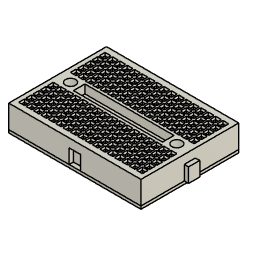
mini_breadboard (Autodesk Fusion 360 design; units mm, degrees)
Autodesk Fusion 360 part; units mm, degrees
(part 1 of 2)
sketch "Sketch1" plane through (0, 0, 0) normal (0, 1, 0) x (1, 0, 0)
  line L0 (0, 0) -> (46, 0)
  line L1 (46, 0) -> (46, -8)
  line L2 (46, -8) -> (0, -8)
  line L3 (0, -8) -> (0, 0)
  dimension "d3" = 46
  dimension "d4" = 8
  constraint horizontal L0
  constraint vertical L1
  constraint horizontal L2
  constraint vertical L3
  constraint coincident L0.start L3.end
  measures "d3" distance of L0.start L0.end
  measures "d4" distance of L0.start L2.end
extrude "Extrude1" add sketch "Sketch1" along normal blind 34 makes body 1
sketch "Sketch2" plane through (0, 0, 8) normal (0, 0, 1) x (-1, 0, 0)
  line L0 (0, 0) -> (-46, 0)
  line L1 (-46, 0) -> (-46, -34)
  line L2 (-46, -34) -> (0, -34)
  line L3 (0, -34) -> (0, 0)
  line L4 (-2, -31.5) -> (-3, -31.5)
  line L5 (-3, -31.5) -> (-3, -30.5)
  line L6 (-3, -30.5) -> (-2, -30.5)
  line L7 (-2, -30.5) -> (-2, -31.5)
  dimension "d11" = 1
  dimension "d12" = 1
  dimension "d38" = 2
  dimension "d39" = 2.5
  constraint horizontal L4
  constraint vertical L5
  constraint horizontal L6
  constraint vertical L7
  measures "d11" distance of L4.end L5.end
  measures "d12" distance of L5.end L6.end
  measures "d38" distance of L3 L7
  measures "d39" distance of L2 L4
extrude "Extrude2" cut sketch "Sketch2" against normal blind 3 contours L4 L5 L6 L7 bodies 1
chamfer "Chamfer1" distance 0.5 angle 45 4 edges at (2.5, 30.5, 8) (3, 31, 8) (2.5, 31.5, 8) (2, 31, 8) on bodies 1
pattern_linear "R-Pattern1" count 17 spacing 2.5625 along (1, 0, 0) count 5 spacing 2.5 along (0, -1, 0) of 9 faces at (2.6667, 31.8333, 7.8333) (1.6667, 31.1667, 7.8333) (2.3333, 31.5, 6.6667) (3.3333, 30.8333, 7.8333) (2.3333, 30.1667, 7.8333) (2.3333, 31.1667, 5) (3, 30.8333, 5.8333) (2.6667, 30.5, 6.6667) (2, 31.1667, 5.8333) on bodies 1
sketch "Sketch3" plane through (0, 0, 8) normal (0, 0, 1) x (-1, 0, 0)
  line L0 (-42.5, -22) -> (-44.5, -22)
  line L1 (-44.5, -22) -> (-44.5, -20)
  line L2 (-44.5, -20) -> (-42.5, -20)
  line L3 (-42.5, -20) -> (-42.5, -22)
  line L4 (-39.9375, -22) -> (-41.9375, -22)
  line L5 (-41.9375, -22) -> (-41.9375, -20)
  line L6 (-41.9375, -20) -> (-39.9375, -20)
  line L7 (-39.9375, -20) -> (-39.9375, -22)
  line L8 (-37.375, -22) -> (-39.375, -22)
  line L9 (-39.375, -22) -> (-39.375, -20)
  line L10 (-39.375, -20) -> (-37.375, -20)
  line L11 (-37.375, -20) -> (-37.375, -22)
  line L12 (-34.8125, -22) -> (-36.8125, -22)
  line L13 (-36.8125, -22) -> (-36.8125, -20)
  line L14 (-36.8125, -20) -> (-34.8125, -20)
  line L15 (-34.8125, -20) -> (-34.8125, -22)
  line L16 (-32.25, -22) -> (-34.25, -22)
  line L17 (-34.25, -22) -> (-34.25, -20)
  line L18 (-34.25, -20) -> (-32.25, -20)
  line L19 (-32.25, -20) -> (-32.25, -22)
  line L20 (-29.6875, -22) -> (-31.6875, -22)
  line L21 (-31.6875, -22) -> (-31.6875, -20)
  line L22 (-31.6875, -20) -> (-29.6875, -20)
  line L23 (-29.6875, -20) -> (-29.6875, -22)
  line L24 (-27.125, -22) -> (-29.125, -22)
  line L25 (-29.125, -22) -> (-29.125, -20)
  line L26 (-29.125, -20) -> (-27.125, -20)
  line L27 (-27.125, -20) -> (-27.125, -22)
  line L28 (-24.5625, -22) -> (-26.5625, -22)
  line L29 (-26.5625, -22) -> (-26.5625, -20)
  line L30 (-26.5625, -20) -> (-24.5625, -20)
  line L31 (-24.5625, -20) -> (-24.5625, -22)
  line L32 (-22, -22) -> (-24, -22)
  line L33 (-24, -22) -> (-24, -20)
  line L34 (-24, -20) -> (-22, -20)
  line L35 (-22, -20) -> (-22, -22)
  line L36 (-19.4375, -22) -> (-21.4375, -22)
  line L37 (-21.4375, -22) -> (-21.4375, -20)
  line L38 (-21.4375, -20) -> (-19.4375, -20)
  line L39 (-19.4375, -20) -> (-19.4375, -22)
  line L40 (-16.875, -22) -> (-18.875, -22)
  line L41 (-18.875, -22) -> (-18.875, -20)
  line L42 (-18.875, -20) -> (-16.875, -20)
  line L43 (-16.875, -20) -> (-16.875, -22)
  line L44 (-14.3125, -22) -> (-16.3125, -22)
  line L45 (-16.3125, -22) -> (-16.3125, -20)
  line L46 (-16.3125, -20) -> (-14.3125, -20)
  line L47 (-14.3125, -20) -> (-14.3125, -22)
  line L48 (-11.75, -22) -> (-13.75, -22)
  line L49 (-13.75, -22) -> (-13.75, -20)
  line L50 (-13.75, -20) -> (-11.75, -20)
  line L51 (-11.75, -20) -> (-11.75, -22)
  line L52 (-9.1875, -22) -> (-11.1875, -22)
  line L53 (-11.1875, -22) -> (-11.1875, -20)
  line L54 (-11.1875, -20) -> (-9.1875, -20)
  line L55 (-9.1875, -20) -> (-9.1875, -22)
  line L56 (-6.625, -22) -> (-8.625, -22)
  line L57 (-8.625, -22) -> (-8.625, -20)
  line L58 (-8.625, -20) -> (-6.625, -20)
  line L59 (-6.625, -20) -> (-6.625, -22)
  line L60 (-4.0625, -22) -> (-6.0625, -22)
  line L61 (-6.0625, -22) -> (-6.0625, -20)
  line L62 (-6.0625, -20) -> (-4.0625, -20)
  line L63 (-4.0625, -20) -> (-4.0625, -22)
  line L64 (-1.5, -22) -> (-3.5, -22)
  line L65 (-3.5, -22) -> (-3.5, -20)
  line L66 (-3.5, -20) -> (-1.5, -20)
  line L67 (-1.5, -20) -> (-1.5, -22)
  line L68 (-42.5, -24.5) -> (-44.5, -24.5)
  line L69 (-44.5, -24.5) -> (-44.5, -22.5)
  line L70 (-44.5, -22.5) -> (-42.5, -22.5)
  line L71 (-42.5, -22.5) -> (-42.5, -24.5)
  line L72 (-39.9375, -24.5) -> (-41.9375, -24.5)
  line L73 (-41.9375, -24.5) -> (-41.9375, -22.5)
  line L74 (-41.9375, -22.5) -> (-39.9375, -22.5)
  line L75 (-39.9375, -22.5) -> (-39.9375, -24.5)
  line L76 (-37.375, -24.5) -> (-39.375, -24.5)
  line L77 (-39.375, -24.5) -> (-39.375, -22.5)
  line L78 (-39.375, -22.5) -> (-37.375, -22.5)
  line L79 (-37.375, -22.5) -> (-37.375, -24.5)
  line L80 (-34.8125, -24.5) -> (-36.8125, -24.5)
  line L81 (-36.8125, -24.5) -> (-36.8125, -22.5)
  line L82 (-36.8125, -22.5) -> (-34.8125, -22.5)
  line L83 (-34.8125, -22.5) -> (-34.8125, -24.5)
  line L84 (-32.25, -24.5) -> (-34.25, -24.5)
  line L85 (-34.25, -24.5) -> (-34.25, -22.5)
  line L86 (-34.25, -22.5) -> (-32.25, -22.5)
  line L87 (-32.25, -22.5) -> (-32.25, -24.5)
  line L88 (-29.6875, -24.5) -> (-31.6875, -24.5)
  line L89 (-31.6875, -24.5) -> (-31.6875, -22.5)
  line L90 (-31.6875, -22.5) -> (-29.6875, -22.5)
  line L91 (-29.6875, -22.5) -> (-29.6875, -24.5)
  line L92 (-27.125, -24.5) -> (-29.125, -24.5)
  line L93 (-29.125, -24.5) -> (-29.125, -22.5)
  line L94 (-29.125, -22.5) -> (-27.125, -22.5)
  line L95 (-27.125, -22.5) -> (-27.125, -24.5)
  line L96 (-24.5625, -24.5) -> (-26.5625, -24.5)
  line L97 (-26.5625, -24.5) -> (-26.5625, -22.5)
  line L98 (-26.5625, -22.5) -> (-24.5625, -22.5)
  line L99 (-24.5625, -22.5) -> (-24.5625, -24.5)
  line L100 (-22, -24.5) -> (-24, -24.5)
  line L101 (-24, -24.5) -> (-24, -22.5)
  line L102 (-24, -22.5) -> (-22, -22.5)
  line L103 (-22, -22.5) -> (-22, -24.5)
  line L104 (-19.4375, -24.5) -> (-21.4375, -24.5)
  line L105 (-21.4375, -24.5) -> (-21.4375, -22.5)
  line L106 (-21.4375, -22.5) -> (-19.4375, -22.5)
  line L107 (-19.4375, -22.5) -> (-19.4375, -24.5)
  line L108 (-16.875, -24.5) -> (-18.875, -24.5)
  line L109 (-18.875, -24.5) -> (-18.875, -22.5)
  line L110 (-18.875, -22.5) -> (-16.875, -22.5)
  line L111 (-16.875, -22.5) -> (-16.875, -24.5)
  line L112 (-14.3125, -24.5) -> (-16.3125, -24.5)
  line L113 (-16.3125, -24.5) -> (-16.3125, -22.5)
  line L114 (-16.3125, -22.5) -> (-14.3125, -22.5)
  line L115 (-14.3125, -22.5) -> (-14.3125, -24.5)
  line L116 (-11.75, -24.5) -> (-13.75, -24.5)
  line L117 (-13.75, -24.5) -> (-13.75, -22.5)
  line L118 (-13.75, -22.5) -> (-11.75, -22.5)
  line L119 (-11.75, -22.5) -> (-11.75, -24.5)
  line L120 (-9.1875, -24.5) -> (-11.1875, -24.5)
  line L121 (-11.1875, -24.5) -> (-11.1875, -22.5)
  line L122 (-11.1875, -22.5) -> (-9.1875, -22.5)
  line L123 (-9.1875, -22.5) -> (-9.1875, -24.5)
  line L124 (-6.625, -24.5) -> (-8.625, -24.5)
  line L125 (-8.625, -24.5) -> (-8.625, -22.5)
  line L126 (-8.625, -22.5) -> (-6.625, -22.5)
  line L127 (-6.625, -22.5) -> (-6.625, -24.5)
  line L128 (-4.0625, -24.5) -> (-6.0625, -24.5)
  line L129 (-6.0625, -24.5) -> (-6.0625, -22.5)
  line L130 (-6.0625, -22.5) -> (-4.0625, -22.5)
  line L131 (-4.0625, -22.5) -> (-4.0625, -24.5)
  line L132 (-1.5, -24.5) -> (-3.5, -24.5)
  line L133 (-3.5, -24.5) -> (-3.5, -22.5)
  line L134 (-3.5, -22.5) -> (-1.5, -22.5)
  line L135 (-1.5, -22.5) -> (-1.5, -24.5)
  line L136 (-42.5, -27) -> (-44.5, -27)
  line L137 (-44.5, -27) -> (-44.5, -25)
  line L138 (-44.5, -25) -> (-42.5, -25)
  line L139 (-42.5, -25) -> (-42.5, -27)
  line L140 (-39.9375, -27) -> (-41.9375, -27)
  line L141 (-41.9375, -27) -> (-41.9375, -25)
  line L142 (-41.9375, -25) -> (-39.9375, -25)
  line L143 (-39.9375, -25) -> (-39.9375, -27)
  line L144 (-37.375, -27) -> (-39.375, -27)
  line L145 (-39.375, -27) -> (-39.375, -25)
  line L146 (-39.375, -25) -> (-37.375, -25)
  line L147 (-37.375, -25) -> (-37.375, -27)
  line L148 (-34.8125, -27) -> (-36.8125, -27)
  line L149 (-36.8125, -27) -> (-36.8125, -25)
  line L150 (-36.8125, -25) -> (-34.8125, -25)
  line L151 (-34.8125, -25) -> (-34.8125, -27)
  line L152 (-32.25, -27) -> (-34.25, -27)
  line L153 (-34.25, -27) -> (-34.25, -25)
  line L154 (-34.25, -25) -> (-32.25, -25)
  line L155 (-32.25, -25) -> (-32.25, -27)
  line L156 (-29.6875, -27) -> (-31.6875, -27)
  line L157 (-31.6875, -27) -> (-31.6875, -25)
  line L158 (-31.6875, -25) -> (-29.6875, -25)
  line L159 (-29.6875, -25) -> (-29.6875, -27)
  line L160 (-27.125, -27) -> (-29.125, -27)
  line L161 (-29.125, -27) -> (-29.125, -25)
  line L162 (-29.125, -25) -> (-27.125, -25)
  line L163 (-27.125, -25) -> (-27.125, -27)
  line L164 (-24.5625, -27) -> (-26.5625, -27)
  line L165 (-26.5625, -27) -> (-26.5625, -25)
  line L166 (-26.5625, -25) -> (-24.5625, -25)
  line L167 (-24.5625, -25) -> (-24.5625, -27)
  line L168 (-22, -27) -> (-24, -27)
  line L169 (-24, -27) -> (-24, -25)
  line L170 (-24, -25) -> (-22, -25)
  line L171 (-22, -25) -> (-22, -27)
  line L172 (-19.4375, -27) -> (-21.4375, -27)
  line L173 (-21.4375, -27) -> (-21.4375, -25)
  line L174 (-21.4375, -25) -> (-19.4375, -25)
  line L175 (-19.4375, -25) -> (-19.4375, -27)
  line L176 (-16.875, -27) -> (-18.875, -27)
  line L177 (-18.875, -27) -> (-18.875, -25)
  line L178 (-18.875, -25) -> (-16.875, -25)
  line L179 (-16.875, -25) -> (-16.875, -27)
  line L180 (-14.3125, -27) -> (-16.3125, -27)
  line L181 (-16.3125, -27) -> (-16.3125, -25)
  line L182 (-16.3125, -25) -> (-14.3125, -25)
  line L183 (-14.3125, -25) -> (-14.3125, -27)
  line L184 (-11.75, -27) -> (-13.75, -27)
  line L185 (-13.75, -27) -> (-13.75, -25)
  line L186 (-13.75, -25) -> (-11.75, -25)
  line L187 (-11.75, -25) -> (-11.75, -27)
  line L188 (-9.1875, -27) -> (-11.1875, -27)
  line L189 (-11.1875, -27) -> (-11.1875, -25)
  line L190 (-11.1875, -25) -> (-9.1875, -25)
  line L191 (-9.1875, -25) -> (-9.1875, -27)
  line L192 (-6.625, -27) -> (-8.625, -27)
  line L193 (-8.625, -27) -> (-8.625, -25)
  line L194 (-8.625, -25) -> (-6.625, -25)
  line L195 (-6.625, -25) -> (-6.625, -27)
  line L196 (-4.0625, -27) -> (-6.0625, -27)
  line L197 (-6.0625, -27) -> (-6.0625, -25)
  line L198 (-6.0625, -25) -> (-4.0625, -25)
  line L199 (-4.0625, -25) -> (-4.0625, -27)
  line L200 (-1.5, -27) -> (-3.5, -27)
  line L201 (-3.5, -27) -> (-3.5, -25)
  line L202 (-3.5, -25) -> (-1.5, -25)
  line L203 (-1.5, -25) -> (-1.5, -27)
  line L204 (-42.5, -29.5) -> (-44.5, -29.5)
  line L205 (-44.5, -29.5) -> (-44.5, -27.5)
  line L206 (-44.5, -27.5) -> (-42.5, -27.5)
  line L207 (-42.5, -27.5) -> (-42.5, -29.5)
  line L208 (-39.9375, -29.5) -> (-41.9375, -29.5)
  line L209 (-41.9375, -29.5) -> (-41.9375, -27.5)
  line L210 (-41.9375, -27.5) -> (-39.9375, -27.5)
  line L211 (-39.9375, -27.5) -> (-39.9375, -29.5)
  line L212 (-37.375, -29.5) -> (-39.375, -29.5)
  line L213 (-39.375, -29.5) -> (-39.375, -27.5)
  line L214 (-39.375, -27.5) -> (-37.375, -27.5)
  line L215 (-37.375, -27.5) -> (-37.375, -29.5)
  line L216 (-34.8125, -29.5) -> (-36.8125, -29.5)
  line L217 (-36.8125, -29.5) -> (-36.8125, -27.5)
  line L218 (-36.8125, -27.5) -> (-34.8125, -27.5)
  line L219 (-34.8125, -27.5) -> (-34.8125, -29.5)
  line L220 (-32.25, -29.5) -> (-34.25, -29.5)
  line L221 (-34.25, -29.5) -> (-34.25, -27.5)
  line L222 (-34.25, -27.5) -> (-32.25, -27.5)
  line L223 (-32.25, -27.5) -> (-32.25, -29.5)
  line L224 (-29.6875, -29.5) -> (-31.6875, -29.5)
  line L225 (-31.6875, -29.5) -> (-31.6875, -27.5)
  line L226 (-31.6875, -27.5) -> (-29.6875, -27.5)
  line L227 (-29.6875, -27.5) -> (-29.6875, -29.5)
  line L228 (-27.125, -29.5) -> (-29.125, -29.5)
  line L229 (-29.125, -29.5) -> (-29.125, -27.5)
  line L230 (-29.125, -27.5) -> (-27.125, -27.5)
  line L231 (-27.125, -27.5) -> (-27.125, -29.5)
  line L232 (-24.5625, -29.5) -> (-26.5625, -29.5)
  line L233 (-26.5625, -29.5) -> (-26.5625, -27.5)
  line L234 (-26.5625, -27.5) -> (-24.5625, -27.5)
  line L235 (-24.5625, -27.5) -> (-24.5625, -29.5)
  line L236 (-22, -29.5) -> (-24, -29.5)
  line L237 (-24, -29.5) -> (-24, -27.5)
  line L238 (-24, -27.5) -> (-22, -27.5)
  line L239 (-22, -27.5) -> (-22, -29.5)
  line L240 (-19.4375, -29.5) -> (-21.4375, -29.5)
  line L241 (-21.4375, -29.5) -> (-21.4375, -27.5)
  line L242 (-21.4375, -27.5) -> (-19.4375, -27.5)
  line L243 (-19.4375, -27.5) -> (-19.4375, -29.5)
  line L244 (-16.875, -29.5) -> (-18.875, -29.5)
  line L245 (-18.875, -29.5) -> (-18.875, -27.5)
  line L246 (-18.875, -27.5) -> (-16.875, -27.5)
  line L247 (-16.875, -27.5) -> (-16.875, -29.5)
  line L248 (-14.3125, -29.5) -> (-16.3125, -29.5)
  line L249 (-16.3125, -29.5) -> (-16.3125, -27.5)
  line L250 (-16.3125, -27.5) -> (-14.3125, -27.5)
  line L251 (-14.3125, -27.5) -> (-14.3125, -29.5)
  line L252 (-11.75, -29.5) -> (-13.75, -29.5)
  line L253 (-13.75, -29.5) -> (-13.75, -27.5)
  line L254 (-13.75, -27.5) -> (-11.75, -27.5)
  line L255 (-11.75, -27.5) -> (-11.75, -29.5)
  line L256 (-9.1875, -29.5) -> (-11.1875, -29.5)
  line L257 (-11.1875, -29.5) -> (-11.1875, -27.5)
  line L258 (-11.1875, -27.5) -> (-9.1875, -27.5)
  line L259 (-9.1875, -27.5) -> (-9.1875, -29.5)
  line L260 (-6.625, -29.5) -> (-8.625, -29.5)
  line L261 (-8.625, -29.5) -> (-8.625, -27.5)
  line L262 (-8.625, -27.5) -> (-6.625, -27.5)
  line L263 (-6.625, -27.5) -> (-6.625, -29.5)
  line L264 (-4.0625, -29.5) -> (-6.0625, -29.5)
  line L265 (-6.0625, -29.5) -> (-6.0625, -27.5)
  line L266 (-6.0625, -27.5) -> (-4.0625, -27.5)
  line L267 (-4.0625, -27.5) -> (-4.0625, -29.5)
  line L268 (-1.5, -29.5) -> (-3.5, -29.5)
  line L269 (-3.5, -29.5) -> (-3.5, -27.5)
  line L270 (-3.5, -27.5) -> (-1.5, -27.5)
  line L271 (-1.5, -27.5) -> (-1.5, -29.5)
  line L272 (-42.5, -32) -> (-44.5, -32)
  line L273 (-44.5, -32) -> (-44.5, -30)
  line L274 (-44.5, -30) -> (-42.5, -30)
  line L275 (-42.5, -30) -> (-42.5, -32)
  line L276 (-39.9375, -32) -> (-41.9375, -32)
  line L277 (-41.9375, -32) -> (-41.9375, -30)
  line L278 (-41.9375, -30) -> (-39.9375, -30)
  line L279 (-39.9375, -30) -> (-39.9375, -32)
  line L280 (-37.375, -32) -> (-39.375, -32)
  line L281 (-39.375, -32) -> (-39.375, -30)
  line L282 (-39.375, -30) -> (-37.375, -30)
  line L283 (-37.375, -30) -> (-37.375, -32)
  line L284 (-34.8125, -32) -> (-36.8125, -32)
  line L285 (-36.8125, -32) -> (-36.8125, -30)
  line L286 (-36.8125, -30) -> (-34.8125, -30)
  line L287 (-34.8125, -30) -> (-34.8125, -32)
  line L288 (-32.25, -32) -> (-34.25, -32)
  line L289 (-34.25, -32) -> (-34.25, -30)
  line L290 (-34.25, -30) -> (-32.25, -30)
  line L291 (-32.25, -30) -> (-32.25, -32)
  line L292 (-29.6875, -32) -> (-31.6875, -32)
  line L293 (-31.6875, -32) -> (-31.6875, -30)
  line L294 (-31.6875, -30) -> (-29.6875, -30)
  line L295 (-29.6875, -30) -> (-29.6875, -32)
  line L296 (-27.125, -32) -> (-29.125, -32)
  line L297 (-29.125, -32) -> (-29.125, -30)
  line L298 (-29.125, -30) -> (-27.125, -30)
  line L299 (-27.125, -30) -> (-27.125, -32)
  line L300 (-24.5625, -32) -> (-26.5625, -32)
  line L301 (-26.5625, -32) -> (-26.5625, -30)
  line L302 (-26.5625, -30) -> (-24.5625, -30)
  line L303 (-24.5625, -30) -> (-24.5625, -32)
  line L304 (-22, -32) -> (-24, -32)
  line L305 (-24, -32) -> (-24, -30)
  line L306 (-24, -30) -> (-22, -30)
  line L307 (-22, -30) -> (-22, -32)
  line L308 (-19.4375, -32) -> (-21.4375, -32)
  line L309 (-21.4375, -32) -> (-21.4375, -30)
  line L310 (-21.4375, -30) -> (-19.4375, -30)
  line L311 (-19.4375, -30) -> (-19.4375, -32)
  line L312 (-16.875, -32) -> (-18.875, -32)
  line L313 (-18.875, -32) -> (-18.875, -30)
  line L314 (-18.875, -30) -> (-16.875, -30)
  line L315 (-16.875, -30) -> (-16.875, -32)
  line L316 (-14.3125, -32) -> (-16.3125, -32)
  line L317 (-16.3125, -32) -> (-16.3125, -30)
  line L318 (-16.3125, -30) -> (-14.3125, -30)
  line L319 (-14.3125, -30) -> (-14.3125, -32)
  line L320 (-11.75, -32) -> (-13.75, -32)
  line L321 (-13.75, -32) -> (-13.75, -30)
  line L322 (-13.75, -30) -> (-11.75, -30)
  line L323 (-11.75, -30) -> (-11.75, -32)
  line L324 (-9.1875, -32) -> (-11.1875, -32)
  line L325 (-11.1875, -32) -> (-11.1875, -30)
  line L326 (-11.1875, -30) -> (-9.1875, -30)
  line L327 (-9.1875, -30) -> (-9.1875, -32)
  line L328 (-6.625, -32) -> (-8.625, -32)
  line L329 (-8.625, -32) -> (-8.625, -30)
  line L330 (-8.625, -30) -> (-6.625, -30)
  line L331 (-6.625, -30) -> (-6.625, -32)
  line L332 (-4.0625, -32) -> (-6.0625, -32)
  line L333 (-6.0625, -32) -> (-6.0625, -30)
  line L334 (-6.0625, -30) -> (-4.0625, -30)
  line L335 (-4.0625, -30) -> (-4.0625, -32)
  line L336 (0, 0) -> (-46, 0)
  line L337 (-46, 0) -> (-46, -34)
  line L338 (-46, -34) -> (0, -34)
  line L339 (0, -34) -> (0, 0)
  line L340 (-1.5, -32) -> (-3.5, -32)
  line L341 (-3.5, -32) -> (-3.5, -30)
  line L342 (-3.5, -30) -> (-1.5, -30)
  line L343 (-1.5, -30) -> (-1.5, -32)
  line L344 (-38.5, -15) -> (-7.5, -15)
  line L345 (-7.5, -15) -> (-7.5, -19)
  line L346 (-7.5, -19) -> (-38.5, -19)
  line L347 (-38.5, -19) -> (-38.5, -15)
  dimension "d21" = 31
  dimension "d22" = 4
  dimension "d23" = 7.5
  dimension "d24" = 1
  constraint horizontal L344
  constraint vertical L345
  constraint horizontal L346
  constraint vertical L347
  measures "d21" distance of L344.start L344.end
  measures "d22" distance of L344.end L345.end
  measures "d23" distance of L337 L347
  measures "d24" distance of L38 L346
extrude "Extrude3" cut sketch "Sketch3" against normal blind 3 contours L344 L345 L346 L347 bodies 1
sketch "Sketch4" plane through (0, 0, 8) normal (0, 0, 1) x (-1, 0, 0)
  line L0 (-7.5, -15) -> (-7.5, -19)
  line L1 (-7.5, -19) -> (-38.5, -19)
  line L2 (-38.5, -19) -> (-38.5, -15)
  line L3 (-38.5, -15) -> (-7.5, -15)
  line L4 (-42.5, -22) -> (-44.5, -22)
  line L5 (-44.5, -22) -> (-44.5, -20)
  line L6 (-44.5, -20) -> (-42.5, -20)
  line L7 (-42.5, -20) -> (-42.5, -22)
  line L8 (-39.9375, -22) -> (-41.9375, -22)
  line L9 (-41.9375, -22) -> (-41.9375, -20)
  line L10 (-41.9375, -20) -> (-39.9375, -20)
  line L11 (-39.9375, -20) -> (-39.9375, -22)
  line L12 (-37.375, -22) -> (-39.375, -22)
  line L13 (-39.375, -22) -> (-39.375, -20)
  line L14 (-39.375, -20) -> (-37.375, -20)
  line L15 (-37.375, -20) -> (-37.375, -22)
  line L16 (-34.8125, -22) -> (-36.8125, -22)
  line L17 (-36.8125, -22) -> (-36.8125, -20)
  line L18 (-36.8125, -20) -> (-34.8125, -20)
  line L19 (-34.8125, -20) -> (-34.8125, -22)
  line L20 (-32.25, -22) -> (-34.25, -22)
  line L21 (-34.25, -22) -> (-34.25, -20)
  line L22 (-34.25, -20) -> (-32.25, -20)
  line L23 (-32.25, -20) -> (-32.25, -22)
  line L24 (-29.6875, -22) -> (-31.6875, -22)
  line L25 (-31.6875, -22) -> (-31.6875, -20)
  line L26 (-31.6875, -20) -> (-29.6875, -20)
  line L27 (-29.6875, -20) -> (-29.6875, -22)
  line L28 (-27.125, -22) -> (-29.125, -22)
  line L29 (-29.125, -22) -> (-29.125, -20)
  line L30 (-29.125, -20) -> (-27.125, -20)
  line L31 (-27.125, -20) -> (-27.125, -22)
  line L32 (-24.5625, -22) -> (-26.5625, -22)
  line L33 (-26.5625, -22) -> (-26.5625, -20)
  line L34 (-26.5625, -20) -> (-24.5625, -20)
  line L35 (-24.5625, -20) -> (-24.5625, -22)
  line L36 (-22, -22) -> (-24, -22)
  line L37 (-24, -22) -> (-24, -20)
  line L38 (-24, -20) -> (-22, -20)
  line L39 (-22, -20) -> (-22, -22)
  line L40 (-19.4375, -22) -> (-21.4375, -22)
  line L41 (-21.4375, -22) -> (-21.4375, -20)
  line L42 (-21.4375, -20) -> (-19.4375, -20)
  line L43 (-19.4375, -20) -> (-19.4375, -22)
  line L44 (-16.875, -22) -> (-18.875, -22)
  line L45 (-18.875, -22) -> (-18.875, -20)
  line L46 (-18.875, -20) -> (-16.875, -20)
  line L47 (-16.875, -20) -> (-16.875, -22)
  line L48 (-14.3125, -22) -> (-16.3125, -22)
  line L49 (-16.3125, -22) -> (-16.3125, -20)
  line L50 (-16.3125, -20) -> (-14.3125, -20)
  line L51 (-14.3125, -20) -> (-14.3125, -22)
  line L52 (-11.75, -22) -> (-13.75, -22)
  line L53 (-13.75, -22) -> (-13.75, -20)
  line L54 (-13.75, -20) -> (-11.75, -20)
  line L55 (-11.75, -20) -> (-11.75, -22)
  line L56 (-9.1875, -22) -> (-11.1875, -22)
  line L57 (-11.1875, -22) -> (-11.1875, -20)
  line L58 (-11.1875, -20) -> (-9.1875, -20)
  line L59 (-9.1875, -20) -> (-9.1875, -22)
  line L60 (-6.625, -22) -> (-8.625, -22)
  line L61 (-8.625, -22) -> (-8.625, -20)
  line L62 (-8.625, -20) -> (-6.625, -20)
  line L63 (-6.625, -20) -> (-6.625, -22)
  line L64 (-4.0625, -22) -> (-6.0625, -22)
  line L65 (-6.0625, -22) -> (-6.0625, -20)
  line L66 (-6.0625, -20) -> (-4.0625, -20)
  line L67 (-4.0625, -20) -> (-4.0625, -22)
  line L68 (-1.5, -22) -> (-3.5, -22)
  line L69 (-3.5, -22) -> (-3.5, -20)
  line L70 (-3.5, -20) -> (-1.5, -20)
  line L71 (-1.5, -20) -> (-1.5, -22)
  line L72 (-42.5, -24.5) -> (-44.5, -24.5)
  line L73 (-44.5, -24.5) -> (-44.5, -22.5)
  line L74 (-44.5, -22.5) -> (-42.5, -22.5)
  line L75 (-42.5, -22.5) -> (-42.5, -24.5)
  line L76 (-39.9375, -24.5) -> (-41.9375, -24.5)
  line L77 (-41.9375, -24.5) -> (-41.9375, -22.5)
  line L78 (-41.9375, -22.5) -> (-39.9375, -22.5)
  line L79 (-39.9375, -22.5) -> (-39.9375, -24.5)
  line L80 (-37.375, -24.5) -> (-39.375, -24.5)
  line L81 (-39.375, -24.5) -> (-39.375, -22.5)
  line L82 (-39.375, -22.5) -> (-37.375, -22.5)
  line L83 (-37.375, -22.5) -> (-37.375, -24.5)
  line L84 (-34.8125, -24.5) -> (-36.8125, -24.5)
  line L85 (-36.8125, -24.5) -> (-36.8125, -22.5)
  line L86 (-36.8125, -22.5) -> (-34.8125, -22.5)
  line L87 (-34.8125, -22.5) -> (-34.8125, -24.5)
  line L88 (-32.25, -24.5) -> (-34.25, -24.5)
  line L89 (-34.25, -24.5) -> (-34.25, -22.5)
  line L90 (-34.25, -22.5) -> (-32.25, -22.5)
  line L91 (-32.25, -22.5) -> (-32.25, -24.5)
  line L92 (-29.6875, -24.5) -> (-31.6875, -24.5)
  line L93 (-31.6875, -24.5) -> (-31.6875, -22.5)
  line L94 (-31.6875, -22.5) -> (-29.6875, -22.5)
  line L95 (-29.6875, -22.5) -> (-29.6875, -24.5)
  line L96 (-27.125, -24.5) -> (-29.125, -24.5)
  line L97 (-29.125, -24.5) -> (-29.125, -22.5)
  line L98 (-29.125, -22.5) -> (-27.125, -22.5)
  line L99 (-27.125, -22.5) -> (-27.125, -24.5)
  line L100 (-24.5625, -24.5) -> (-26.5625, -24.5)
  line L101 (-26.5625, -24.5) -> (-26.5625, -22.5)
  line L102 (-26.5625, -22.5) -> (-24.5625, -22.5)
  line L103 (-24.5625, -22.5) -> (-24.5625, -24.5)
  line L104 (-22, -24.5) -> (-24, -24.5)
  line L105 (-24, -24.5) -> (-24, -22.5)
  line L106 (-24, -22.5) -> (-22, -22.5)
  line L107 (-22, -22.5) -> (-22, -24.5)
  line L108 (-19.4375, -24.5) -> (-21.4375, -24.5)
  line L109 (-21.4375, -24.5) -> (-21.4375, -22.5)
  line L110 (-21.4375, -22.5) -> (-19.4375, -22.5)
  line L111 (-19.4375, -22.5) -> (-19.4375, -24.5)
  line L112 (-16.875, -24.5) -> (-18.875, -24.5)
  line L113 (-18.875, -24.5) -> (-18.875, -22.5)
  line L114 (-18.875, -22.5) -> (-16.875, -22.5)
  line L115 (-16.875, -22.5) -> (-16.875, -24.5)
  line L116 (-14.3125, -24.5) -> (-16.3125, -24.5)
  line L117 (-16.3125, -24.5) -> (-16.3125, -22.5)
  line L118 (-16.3125, -22.5) -> (-14.3125, -22.5)
  line L119 (-14.3125, -22.5) -> (-14.3125, -24.5)
  line L120 (-11.75, -24.5) -> (-13.75, -24.5)
  line L121 (-13.75, -24.5) -> (-13.75, -22.5)
  line L122 (-13.75, -22.5) -> (-11.75, -22.5)
  line L123 (-11.75, -22.5) -> (-11.75, -24.5)
  line L124 (-9.1875, -24.5) -> (-11.1875, -24.5)
  line L125 (-11.1875, -24.5) -> (-11.1875, -22.5)
  line L126 (-11.1875, -22.5) -> (-9.1875, -22.5)
  line L127 (-9.1875, -22.5) -> (-9.1875, -24.5)
  line L128 (-6.625, -24.5) -> (-8.625, -24.5)
  line L129 (-8.625, -24.5) -> (-8.625, -22.5)
  line L130 (-8.625, -22.5) -> (-6.625, -22.5)
  line L131 (-6.625, -22.5) -> (-6.625, -24.5)
  line L132 (-4.0625, -24.5) -> (-6.0625, -24.5)
  line L133 (-6.0625, -24.5) -> (-6.0625, -22.5)
  line L134 (-6.0625, -22.5) -> (-4.0625, -22.5)
  line L135 (-4.0625, -22.5) -> (-4.0625, -24.5)
  line L136 (-1.5, -24.5) -> (-3.5, -24.5)
  line L137 (-3.5, -24.5) -> (-3.5, -22.5)
  line L138 (-3.5, -22.5) -> (-1.5, -22.5)
  line L139 (-1.5, -22.5) -> (-1.5, -24.5)
  line L140 (-42.5, -27) -> (-44.5, -27)
  line L141 (-44.5, -27) -> (-44.5, -25)
  line L142 (-44.5, -25) -> (-42.5, -25)
  line L143 (-42.5, -25) -> (-42.5, -27)
  line L144 (-39.9375, -27) -> (-41.9375, -27)
  line L145 (-41.9375, -27) -> (-41.9375, -25)
  line L146 (-41.9375, -25) -> (-39.9375, -25)
  line L147 (-39.9375, -25) -> (-39.9375, -27)
  line L148 (-37.375, -27) -> (-39.375, -27)
  line L149 (-39.375, -27) -> (-39.375, -25)
  line L150 (-39.375, -25) -> (-37.375, -25)
  line L151 (-37.375, -25) -> (-37.375, -27)
  line L152 (-34.8125, -27) -> (-36.8125, -27)
  line L153 (-36.8125, -27) -> (-36.8125, -25)
  line L154 (-36.8125, -25) -> (-34.8125, -25)
  line L155 (-34.8125, -25) -> (-34.8125, -27)
  line L156 (-32.25, -27) -> (-34.25, -27)
  line L157 (-34.25, -27) -> (-34.25, -25)
  line L158 (-34.25, -25) -> (-32.25, -25)
  line L159 (-32.25, -25) -> (-32.25, -27)
  line L160 (-29.6875, -27) -> (-31.6875, -27)
  line L161 (-31.6875, -27) -> (-31.6875, -25)
  line L162 (-31.6875, -25) -> (-29.6875, -25)
  line L163 (-29.6875, -25) -> (-29.6875, -27)
  line L164 (-27.125, -27) -> (-29.125, -27)
  line L165 (-29.125, -27) -> (-29.125, -25)
  line L166 (-29.125, -25) -> (-27.125, -25)
  line L167 (-27.125, -25) -> (-27.125, -27)
  line L168 (-24.5625, -27) -> (-26.5625, -27)
  line L169 (-26.5625, -27) -> (-26.5625, -25)
  line L170 (-26.5625, -25) -> (-24.5625, -25)
  line L171 (-24.5625, -25) -> (-24.5625, -27)
  line L172 (-22, -27) -> (-24, -27)
  line L173 (-24, -27) -> (-24, -25)
  line L174 (-24, -25) -> (-22, -25)
  line L175 (-22, -25) -> (-22, -27)
  line L176 (-19.4375, -27) -> (-21.4375, -27)
  line L177 (-21.4375, -27) -> (-21.4375, -25)
  line L178 (-21.4375, -25) -> (-19.4375, -25)
  line L179 (-19.4375, -25) -> (-19.4375, -27)
  line L180 (-16.875, -27) -> (-18.875, -27)
  line L181 (-18.875, -27) -> (-18.875, -25)
  line L182 (-18.875, -25) -> (-16.875, -25)
  line L183 (-16.875, -25) -> (-16.875, -27)
  line L184 (-14.3125, -27) -> (-16.3125, -27)
  line L185 (-16.3125, -27) -> (-16.3125, -25)
  line L186 (-16.3125, -25) -> (-14.3125, -25)
  line L187 (-14.3125, -25) -> (-14.3125, -27)
  line L188 (-11.75, -27) -> (-13.75, -27)
  line L189 (-13.75, -27) -> (-13.75, -25)
  line L190 (-13.75, -25) -> (-11.75, -25)
  line L191 (-11.75, -25) -> (-11.75, -27)
  line L192 (-9.1875, -27) -> (-11.1875, -27)
  line L193 (-11.1875, -27) -> (-11.1875, -25)
  line L194 (-11.1875, -25) -> (-9.1875, -25)
  line L195 (-9.1875, -25) -> (-9.1875, -27)
  line L196 (-6.625, -27) -> (-8.625, -27)
  line L197 (-8.625, -27) -> (-8.625, -25)
  line L198 (-8.625, -25) -> (-6.625, -25)
  line L199 (-6.625, -25) -> (-6.625, -27)
  line L200 (-4.0625, -27) -> (-6.0625, -27)
  line L201 (-6.0625, -27) -> (-6.0625, -25)
  line L202 (-6.0625, -25) -> (-4.0625, -25)
  line L203 (-4.0625, -25) -> (-4.0625, -27)
  line L204 (-1.5, -27) -> (-3.5, -27)
  line L205 (-3.5, -27) -> (-3.5, -25)
  line L206 (-3.5, -25) -> (-1.5, -25)
  line L207 (-1.5, -25) -> (-1.5, -27)
  line L208 (-42.5, -29.5) -> (-44.5, -29.5)
  line L209 (-44.5, -29.5) -> (-44.5, -27.5)
  line L210 (-44.5, -27.5) -> (-42.5, -27.5)
  line L211 (-42.5, -27.5) -> (-42.5, -29.5)
  line L212 (-39.9375, -29.5) -> (-41.9375, -29.5)
  line L213 (-41.9375, -29.5) -> (-41.9375, -27.5)
  line L214 (-41.9375, -27.5) -> (-39.9375, -27.5)
  line L215 (-39.9375, -27.5) -> (-39.9375, -29.5)
  line L216 (-37.375, -29.5) -> (-39.375, -29.5)
  line L217 (-39.375, -29.5) -> (-39.375, -27.5)
  line L218 (-39.375, -27.5) -> (-37.375, -27.5)
  line L219 (-37.375, -27.5) -> (-37.375, -29.5)
  line L220 (-34.8125, -29.5) -> (-36.8125, -29.5)
  line L221 (-36.8125, -29.5) -> (-36.8125, -27.5)
  line L222 (-36.8125, -27.5) -> (-34.8125, -27.5)
  line L223 (-34.8125, -27.5) -> (-34.8125, -29.5)
  line L224 (-32.25, -29.5) -> (-34.25, -29.5)
  line L225 (-34.25, -29.5) -> (-34.25, -27.5)
  line L226 (-34.25, -27.5) -> (-32.25, -27.5)
  line L227 (-32.25, -27.5) -> (-32.25, -29.5)
  line L228 (-29.6875, -29.5) -> (-31.6875, -29.5)
  line L229 (-31.6875, -29.5) -> (-31.6875, -27.5)
  line L230 (-31.6875, -27.5) -> (-29.6875, -27.5)
  line L231 (-29.6875, -27.5) -> (-29.6875, -29.5)
  line L232 (-27.125, -29.5) -> (-29.125, -29.5)
  line L233 (-29.125, -29.5) -> (-29.125, -27.5)
  line L234 (-29.125, -27.5) -> (-27.125, -27.5)
  line L235 (-27.125, -27.5) -> (-27.125, -29.5)
  line L236 (-24.5625, -29.5) -> (-26.5625, -29.5)
  line L237 (-26.5625, -29.5) -> (-26.5625, -27.5)
  line L238 (-26.5625, -27.5) -> (-24.5625, -27.5)
  line L239 (-24.5625, -27.5) -> (-24.5625, -29.5)
  line L240 (-22, -29.5) -> (-24, -29.5)
  line L241 (-24, -29.5) -> (-24, -27.5)
  line L242 (-24, -27.5) -> (-22, -27.5)
  line L243 (-22, -27.5) -> (-22, -29.5)
  line L244 (-19.4375, -29.5) -> (-21.4375, -29.5)
  line L245 (-21.4375, -29.5) -> (-21.4375, -27.5)
  line L246 (-21.4375, -27.5) -> (-19.4375, -27.5)
  line L247 (-19.4375, -27.5) -> (-19.4375, -29.5)
  line L248 (-16.875, -29.5) -> (-18.875, -29.5)
  line L249 (-18.875, -29.5) -> (-18.875, -27.5)
  line L250 (-18.875, -27.5) -> (-16.875, -27.5)
  line L251 (-16.875, -27.5) -> (-16.875, -29.5)
  line L252 (-14.3125, -29.5) -> (-16.3125, -29.5)
  line L253 (-16.3125, -29.5) -> (-16.3125, -27.5)
  line L254 (-16.3125, -27.5) -> (-14.3125, -27.5)
  line L255 (-14.3125, -27.5) -> (-14.3125, -29.5)
  line L256 (-11.75, -29.5) -> (-13.75, -29.5)
  line L257 (-13.75, -29.5) -> (-13.75, -27.5)
  line L258 (-13.75, -27.5) -> (-11.75, -27.5)
  line L259 (-11.75, -27.5) -> (-11.75, -29.5)
  line L260 (-9.1875, -29.5) -> (-11.1875, -29.5)
  line L261 (-11.1875, -29.5) -> (-11.1875, -27.5)
  line L262 (-11.1875, -27.5) -> (-9.1875, -27.5)
  line L263 (-9.1875, -27.5) -> (-9.1875, -29.5)
  line L264 (-6.625, -29.5) -> (-8.625, -29.5)
  line L265 (-8.625, -29.5) -> (-8.625, -27.5)
  line L266 (-8.625, -27.5) -> (-6.625, -27.5)
  line L267 (-6.625, -27.5) -> (-6.625, -29.5)
  line L268 (-4.0625, -29.5) -> (-6.0625, -29.5)
  line L269 (-6.0625, -29.5) -> (-6.0625, -27.5)
  line L270 (-6.0625, -27.5) -> (-4.0625, -27.5)
  line L271 (-4.0625, -27.5) -> (-4.0625, -29.5)
  line L272 (-1.5, -29.5) -> (-3.5, -29.5)
  line L273 (-3.5, -29.5) -> (-3.5, -27.5)
  line L274 (-3.5, -27.5) -> (-1.5, -27.5)
  line L275 (-1.5, -27.5) -> (-1.5, -29.5)
  line L276 (-42.5, -32) -> (-44.5, -32)
  line L277 (-44.5, -32) -> (-44.5, -30)
  line L278 (-44.5, -30) -> (-42.5, -30)
  line L279 (-42.5, -30) -> (-42.5, -32)
  line L280 (-39.9375, -32) -> (-41.9375, -32)
  line L281 (-41.9375, -32) -> (-41.9375, -30)
  line L282 (-41.9375, -30) -> (-39.9375, -30)
  line L283 (-39.9375, -30) -> (-39.9375, -32)
  line L284 (-37.375, -32) -> (-39.375, -32)
  line L285 (-39.375, -32) -> (-39.375, -30)
  line L286 (-39.375, -30) -> (-37.375, -30)
  line L287 (-37.375, -30) -> (-37.375, -32)
  line L288 (-34.8125, -32) -> (-36.8125, -32)
  line L289 (-36.8125, -32) -> (-36.8125, -30)
  line L290 (-36.8125, -30) -> (-34.8125, -30)
  line L291 (-34.8125, -30) -> (-34.8125, -32)
  line L292 (-32.25, -32) -> (-34.25, -32)
  line L293 (-34.25, -32) -> (-34.25, -30)
  line L294 (-34.25, -30) -> (-32.25, -30)
  line L295 (-32.25, -30) -> (-32.25, -32)
  line L296 (-29.6875, -32) -> (-31.6875, -32)
  line L297 (-31.6875, -32) -> (-31.6875, -30)
  line L298 (-31.6875, -30) -> (-29.6875, -30)
  line L299 (-29.6875, -30) -> (-29.6875, -32)
  line L300 (-27.125, -32) -> (-29.125, -32)
  line L301 (-29.125, -32) -> (-29.125, -30)
  line L302 (-29.125, -30) -> (-27.125, -30)
  line L303 (-27.125, -30) -> (-27.125, -32)
  line L304 (-24.5625, -32) -> (-26.5625, -32)
  line L305 (-26.5625, -32) -> (-26.5625, -30)
  line L306 (-26.5625, -30) -> (-24.5625, -30)
  line L307 (-24.5625, -30) -> (-24.5625, -32)
  line L308 (-22, -32) -> (-24, -32)
  line L309 (-24, -32) -> (-24, -30)
  line L310 (-24, -30) -> (-22, -30)
  line L311 (-22, -30) -> (-22, -32)
  line L312 (-19.4375, -32) -> (-21.4375, -32)
  line L313 (-21.4375, -32) -> (-21.4375, -30)
  line L314 (-21.4375, -30) -> (-19.4375, -30)
  line L315 (-19.4375, -30) -> (-19.4375, -32)
  line L316 (-16.875, -32) -> (-18.875, -32)
  line L317 (-18.875, -32) -> (-18.875, -30)
  line L318 (-18.875, -30) -> (-16.875, -30)
  line L319 (-16.875, -30) -> (-16.875, -32)
  line L320 (-14.3125, -32) -> (-16.3125, -32)
  line L321 (-16.3125, -32) -> (-16.3125, -30)
  line L322 (-16.3125, -30) -> (-14.3125, -30)
  line L323 (-14.3125, -30) -> (-14.3125, -32)
  line L324 (-11.75, -32) -> (-13.75, -32)
  line L325 (-13.75, -32) -> (-13.75, -30)
  line L326 (-13.75, -30) -> (-11.75, -30)
  line L327 (-11.75, -30) -> (-11.75, -32)
  line L328 (-9.1875, -32) -> (-11.1875, -32)
  line L329 (-11.1875, -32) -> (-11.1875, -30)
  line L330 (-11.1875, -30) -> (-9.1875, -30)
  line L331 (-9.1875, -30) -> (-9.1875, -32)
  line L332 (-6.625, -32) -> (-8.625, -32)
  line L333 (-8.625, -32) -> (-8.625, -30)
  line L334 (-8.625, -30) -> (-6.625, -30)
  line L335 (-6.625, -30) -> (-6.625, -32)
  line L336 (-4.0625, -32) -> (-6.0625, -32)
  line L337 (-6.0625, -32) -> (-6.0625, -30)
  line L338 (-6.0625, -30) -> (-4.0625, -30)
  line L339 (-4.0625, -30) -> (-4.0625, -32)
  line L340 (0, 0) -> (-46, 0)
  line L341 (-46, 0) -> (-46, -34)
  line L342 (-46, -34) -> (0, -34)
  line L343 (0, -34) -> (0, 0)
  line L344 (-1.5, -32) -> (-3.5, -32)
  line L345 (-3.5, -32) -> (-3.5, -30)
  line L346 (-3.5, -30) -> (-1.5, -30)
  line L347 (-1.5, -30) -> (-1.5, -32)
  line L348 (-2, -2.5) -> (-3, -2.5)
  line L349 (-3, -2.5) -> (-3, -3.5)
  line L350 (-3, -3.5) -> (-2, -3.5)
  line L351 (-2, -3.5) -> (-2, -2.5)
  dimension "d27" = 1
  dimension "d28" = 1
  dimension "d29" = 2
  dimension "d40" = 2.5
  constraint horizontal L348
  constraint vertical L349
  constraint horizontal L350
  constraint vertical L351
  measures "d27" distance of L348.start L348.end
  measures "d28" distance of L348.start L350.end
  measures "d29" distance of L343 L351
  measures "d40" distance of L340 L348
extrude "Extrude4" cut sketch "Sketch4" against normal blind 3 contours L348 L349 L350 L351 bodies 1
chamfer "Chamfer2" distance 0.5 angle 45 4 edges at (2.5, 2.5, 8) (3, 3, 8) (2.5, 3.5, 8) (2, 3, 8) on bodies 1
pattern_linear "R-Pattern2" count 17 spacing 2.5625 along (1, 0, 0) count 5 spacing 2.5 along (0, 1, 0) of 9 faces at (1.6667, 2.8333, 7.8333) (2.3333, 3.8333, 7.8333) (2.3333, 3.5, 5.8333) (2, 3.1667, 6.6667) (3.3333, 3.1667, 7.8333) (2.6667, 2.1667, 7.8333) (3, 2.8333, 6.6667) (2.3333, 2.5, 6.6667) (2.3333, 3.1667, 5) on bodies 1